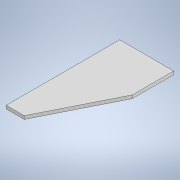
# Autodesk Inventor part: INTARITURA_FRONTAR
Saved by Autodesk Inventor 2022.6 (Build 266554000, 554)
## iProperties
Created: 2025-04-03
Part Number: INTARITURA_FRONTAR
Material: Generic
Document SubType Name: Modeling
Designer: Dragos Macovei
Density: 1 g/cm^3
Appearance: Default
Author: Dragos Macovei
Autodesk Inventor part; units mm, degrees
ref_plane "YZ Plane" through (0, 0, 0) normal (1, 0, 0) x (0, 1, 0)
ref_plane "XZ Plane" through (0, 0, 0) normal (0, 1, 0) x (-1, 0, 0)
ref_plane "XY Plane" through (0, 0, 0) normal (0, 0, 1) x (1, 0, 0)
sketch "Sketch1" plane through (0, 0, 0) normal (0, 1, 0) x (-1, 0, 0)
  line L0 (0, 0) -> (300, 0)
  line L1 (300, 0) -> (300, 630)
  line L2 (300, 630) -> (200, 630)
  line L3 (0, 230) -> (0, 0)
  line L4 (200, 630) -> (0, 230)
  dimension "d0" = 300
  dimension "d1" = 630
  dimension "d4" = 400
  dimension "d5" = 100
  constraints: 10 end point, 2 parallel, 1 horizontal, 1 perpendicular
  measures "d0" distance between parallel lines of L3 L1
  measures "d1" distance between parallel lines of L0 L2
  measures "d4" distance from line of L3.start L2
  measures "d5" distance from line of L2.end L1
extrude "Extrusion1" add sketch "Sketch1" along normal blind 18
body "Solid1"
